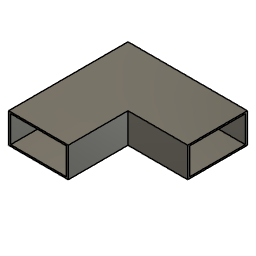
90degreesangle (Autodesk Fusion 360 design; units mm, degrees)
Autodesk Fusion 360 part; units mm, degrees
sketch "Sketch1" plane through (0, 0, 0) normal (0, 1, 0) x (1, 0, 0)
  line L0 (0, 0) -> (60, 0)
  line L1 (60, 0) -> (60, 60)
  line L2 (60, 60) -> (0, 60)
  line L3 (0, 60) -> (0, 0)
  dimension "d1" = 60
  dimension "d2" = 60
  constraint horizontal L0
  constraint vertical L1
  constraint horizontal L2
  constraint vertical L3
  constraint coincident L0.start L3.end
  measures "d1" distance of L0.start L0.end
  measures "d2" distance of L0.start L2.end
extrude "Extrude1" add sketch "Sketch1" along normal blind 15 makes body 1
sketch "Sketch2" plane through (0, 0, 0) normal (0, -1, 0) x (1, 0, 0)
  line L0 (0, 0) -> (0, -60)
  line L1 (0, -60) -> (60, -60)
  line L2 (60, -60) -> (60, 0)
  line L3 (60, 0) -> (0, 0)
  line L4 (30, 0) -> (60, 0)
  line L5 (60, 0) -> (60, -30)
  line L6 (60, -30) -> (30, -30)
  line L7 (30, -30) -> (30, 0)
  constraint horizontal L4
  constraint vertical L5
  constraint horizontal L6
  constraint vertical L7
  constraint midpoint L2 L5.end
  constraint midpoint L3 L4.start
extrude "Extrude2" cut sketch "Sketch2" against normal blind 15 contours L2 L3 L4 L5 L6 L7 bodies 1
sketch "Sketch3" plane through (0, 0, 0) normal (0, -1, 0) x (1, 0, 0)
  line L0 (30, -30) -> (30, 0)
  line L1 (30, 0) -> (0, 0)
  line L2 (0, 0) -> (0, -60)
  line L3 (0, -60) -> (60, -60)
  line L4 (60, -60) -> (60, -30)
  line L5 (60, -30) -> (30, -30)
  line L6 (30, -30) -> (0, -30)
  line L7 (30, -30) -> (30, -60)
  line L8 (1, -31) -> (29, -31)
  line L9 (29, -31) -> (29, -59)
  line L10 (29, -59) -> (1, -59)
  line L11 (1, -59) -> (1, -31)
  line L12 (1, -31) -> (1, -30)
  line L13 (29, -31) -> (30, -31)
  line L14 (1, -59) -> (1, -60)
  line L15 (1, -59) -> (0, -59)
  dimension "d7" = 28
  dimension "d8" = 28
  constraint coincident L0.start L5.end
  constraint midpoint L2 L6.end
  constraint midpoint L3 L7.end
  constraint horizontal L8
  constraint vertical L9
  constraint horizontal L10
  constraint vertical L11
  constraint coincident L6 L12.end
  constraint perpendicular L6 L12
  constraint coincident L7 L13.end
  constraint perpendicular L7 L13
  constraint coincident L3 L14.end
  constraint perpendicular L3 L14
  constraint coincident L2 L15.end
  constraint perpendicular L2 L15
  constraint equal L13 L15
  constraint equal L12 L14
  measures "d7" distance of L8.start L8.end
  measures "d8" distance of L8.start L10.end
extrude "Extrude3" cut sketch "Sketch3" against normal blind 14 contours L8 L9 L10 L11 bodies 1
sketch "Sketch4" plane through (0, 0, 0) normal (0, 0, 1) x (1, 0, 0)
  line L0 (30, 0) -> (30, 15)
  line L1 (30, 15) -> (0, 15)
  line L2 (0, 15) -> (0, 0)
  line L3 (0, 0) -> (30, 0)
  line L4 (1, 14.25) -> (29, 14.25)
  line L5 (29, 14.25) -> (29, 0.75)
  line L6 (29, 0.75) -> (1, 0.75)
  line L7 (1, 0.75) -> (1, 14.25)
  line L8 (1, 14.25) -> (1, 15)
  line L9 (29, 14.25) -> (30, 14.25)
  line L10 (29, 0.75) -> (29, 0)
  line L11 (1, 0.75) -> (0, 0.75)
  dimension "d11" = 28
  dimension "d12" = 13.5
  constraint horizontal L4
  constraint vertical L5
  constraint horizontal L6
  constraint vertical L7
  constraint coincident L1 L8.end
  constraint perpendicular L1 L8
  constraint coincident L0 L9.end
  constraint perpendicular L0 L9
  constraint coincident L3 L10.end
  constraint perpendicular L3 L10
  constraint coincident L2 L11.end
  constraint perpendicular L2 L11
  constraint equal L8 L10
  constraint equal L9 L11
  measures "d11" distance of L4.start L4.end
  measures "d12" distance of L4.start L6.end
extrude "Extrude4" cut sketch "Sketch4" against normal blind 30 contours L4 L5 L6 L7 bodies 1
sketch "Sketch5" plane through (60, 0, 0) normal (1, 0, 0) x (0, 0, -1)
  line L0 (30, 15) -> (30, 0)
  line L1 (30, 0) -> (60, 0)
  line L2 (60, 0) -> (60, 15)
  line L3 (60, 15) -> (30, 15)
  line L4 (31, 14.25) -> (59, 14.25)
  line L5 (59, 14.25) -> (59, 0.75)
  line L6 (59, 0.75) -> (31, 0.75)
  line L7 (31, 0.75) -> (31, 14.25)
  line L8 (31, 14.25) -> (31, 15)
  line L9 (59, 14.25) -> (60, 14.25)
  line L10 (59, 0.75) -> (59, 0)
  line L11 (31, 0.75) -> (30, 0.75)
  dimension "d15" = 28
  dimension "d16" = 13.5
  constraint horizontal L4
  constraint vertical L5
  constraint horizontal L6
  constraint vertical L7
  constraint coincident L3 L8.end
  constraint perpendicular L3 L8
  constraint coincident L2 L9.end
  constraint perpendicular L2 L9
  constraint coincident L1 L10.end
  constraint perpendicular L1 L10
  constraint coincident L0 L11.end
  constraint perpendicular L0 L11
  constraint equal L8 L10
  constraint equal L9 L11
  measures "d15" distance of L4.start L4.end
  measures "d16" distance of L4.start L6.end
extrude "Extrude5" cut sketch "Sketch5" against normal blind 30 contours L4 L5 L6 L7 bodies 1
sketch "Sketch6" plane through (30, 0, 0) normal (1, 0, 0) x (0, 0, -1)
  line L0 (31, 0.75) -> (59, 0.75)
  line L1 (59, 0.75) -> (59, 14.25)
  line L2 (59, 14.25) -> (31, 14.25)
  line L3 (31, 14.25) -> (31, 0.75)
  line L4 (31, 0.75) -> (59, 0.75)
  line L5 (59, 0.75) -> (59, 10.75)
  line L6 (59, 10.75) -> (31, 10.75)
  line L7 (31, 10.75) -> (31, 0.75)
  dimension "d19" = 10
  constraint horizontal L4
  constraint vertical L5
  constraint horizontal L6
  constraint vertical L7
  constraint coincident L0.start L3.end
  measures "d19" distance of L0.start L6.end
extrude "Extrude6" cut sketch "Sketch6" against normal blind 5 contours L0 L1 L3 L4 L5 L6 L7 bodies 1
sketch "Sketch7" plane through (0, 0, -30) normal (0, 0, 1) x (1, 0, 0)
  line L0 (1, 0.75) -> (29, 0.75)
  line L1 (29, 0.75) -> (29, 14.25)
  line L2 (29, 14.25) -> (1, 14.25)
  line L3 (1, 14.25) -> (1, 0.75)
  line L4 (1, 0.75) -> (29, 0.75)
  line L5 (29, 0.75) -> (29, 10.75)
  line L6 (29, 10.75) -> (1, 10.75)
  line L7 (1, 10.75) -> (1, 0.75)
  dimension "d22" = 10
  constraint horizontal L4
  constraint vertical L5
  constraint horizontal L6
  constraint vertical L7
  constraint coincident L1 L5.end
  constraint coincident L0.start L3.end
  measures "d22" distance of L0.start L6.end
extrude "Extrude7" cut sketch "Sketch7" against normal blind 5 contours L0 L1 L3 L4 L5 L6 L7 bodies 1
copy_body "Body->Comp1" bodies 1 removing the originals makes body 2 in component "Component"
component "Component" placed x (1, 0, 0) y (0, 1, 0) z (0, 0, 1) at (0, 0, 0)
